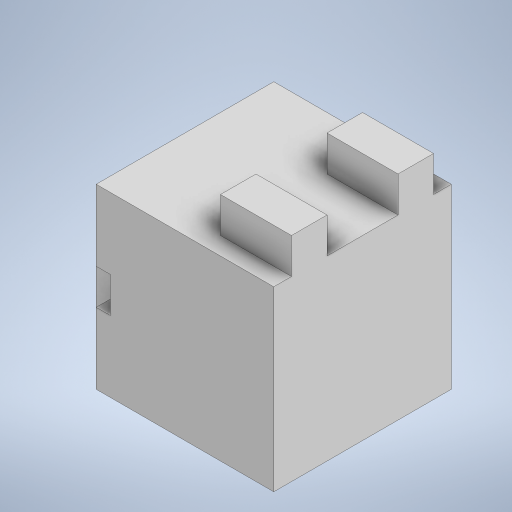
# Autodesk Inventor part: hlava
Saved by Autodesk Inventor 2024 (Build 280153000, 153)
## iProperties
Created: 2025-11-04
Part Number: hlava
Material: Všeobecné
Document SubType Name: Modeling
Designer: zak
Density: 1 g/cm^3
Appearance: Výchozí
Author: zak
Autodesk Inventor part; units mm, degrees
ref_plane "YZ Plane" through (0, 0, 0) normal (1, 0, 0) x (0, 1, 0)
ref_plane "XZ Plane" through (0, 0, 0) normal (0, 1, 0) x (-1, 0, 0)
ref_plane "XY Plane" through (0, 0, 0) normal (0, 0, 1) x (1, 0, 0)
sketch "Náčrt1" plane through (0, 0, 0) normal (0, 0, 1) x (1, 0, 0)
  point P0 (0, 0)
sketch "Náčrt2" plane through (0, 0, 0) normal (0, 0, 1) x (1, 0, 0)
  line L0 (-12.5, 12.5) -> (12.5, 12.5)
  line L1 (12.5, 12.5) -> (12.5, -12.5)
  line L2 (12.5, -12.5) -> (-12.5, -12.5)
  line L3 (-12.5, -12.5) -> (-12.5, 12.5)
  line L4 (-17.5, 0) -> (17.5, 0) projected
  line L5 (0, -17.5) -> (0, 17.5) projected
  point P0 (0, 0)
  dimension "d0" = 25
  dimension "d1" = 25
  constraints: 8 end point, 2 parallel, 1 horizontal, 1 perpendicular, 2 other
  measures "d0" distance of L1.end L2.end
  measures "d1" distance of L0.end L1.end
extrude "Vysunutí1" add sketch "Náčrt2" along normal mid plane 25
sketch "Náčrt3" plane through (-12.5, -12.5, 12.5) normal (-1, 0, 0) x (0, 0, 1)
  line L0 (-25, 0) -> (0, 0) projected
  line L1 (-20, 10) -> (-5, 10)
  line L2 (-5, 10) -> (-5, 0)
  line L3 (-5, 0) -> (-20, 0)
  line L4 (-20, 0) -> (-20, 10)
  line L5 (-12.5, -5) -> (-12.5, 30) projected
  point P0 (-12.5, 12.5)
  point P1 (-20, 0)
  dimension "d4" = 15
  dimension "d5" = 10
  constraints: 8 end point, 2 parallel, 1 horizontal, 1 perpendicular, 1 point on line, 1 other
  measures "d4" distance between parallel lines of L2 L4
  measures "d5" distance between parallel lines of L0 L1
extrude "Vysunutí2" add sketch "Náčrt3" along normal blind 5
sketch "Náčrt4" plane through (-12.5, 12.5, 12.5) normal (0, 1, 0) x (1, 0, 0)
  line L0 (25, 22.5) -> (15, 22.5)
  line L1 (15, 22.5) -> (15, 17.5)
  line L2 (15, 17.5) -> (25, 17.5)
  line L3 (25, 17.5) -> (25, 22.5)
  line L4 (0, 25) -> (25, 25) projected
  line L5 (25, 0) -> (25, 25) projected
  line L6 (-11, 12.5) -> (31, 12.5) projected
  line L7 (25, 2.5) -> (15, 2.5)
  line L8 (15, 2.5) -> (15, 7.5)
  line L9 (15, 7.5) -> (25, 7.5)
  line L10 (25, 7.5) -> (25, 2.5)
  point P0 (12.5, 12.5)
  dimension "d8" = 10
  dimension "d9" = 5
  dimension "d10" = 2.5
  constraints: 16 end point, 4 symmetric about line, 2 parallel, 1 collinear, 1 horizontal, 1 perpendicular
  measures "d8" distance of L2.end L1.end
  measures "d9" distance of L1.end L0.end
  measures "d10" distance between parallel lines of L4 L0
extrude "Vysunutí3" add sketch "Náčrt4" along normal blind 5
sketch "Náčrt5" plane through (-17.5, -12.5, 12.5) normal (-1, 0, 0) x (0, 0, 1)
  line L0 (-12.5, -6) -> (-12.5, 36) projected
  line L1 (-15, 10) -> (-10, 10)
  line L2 (-10, 10) -> (-10, 5)
  line L3 (-10, 5) -> (-15, 5)
  line L4 (-15, 5) -> (-15, 10)
  line L5 (-5, 10) -> (-20, 10) projected
  point P0 (-12.5, 12.5)
  dimension "d17" = 5
  dimension "d18" = 5
  constraints: 8 end point, 2 parallel, 1 collinear, 1 horizontal, 1 perpendicular, 1 other
  measures "d17" distance of L2.end L3.end
  measures "d18" distance of L1.end L2.end
emboss "Reliéf2" sketch "Náčrt5" operation cut depth 1 direction (1, 0, 0)
sketch "Náčrt6" plane through (-12.5, -12.5, 12.5) normal (-1, 0, 0) x (0, 0, 1)
  line L0 (-25, 15) -> (-15, 15)
  line L1 (-15, 15) -> (-15, 10)
  line L2 (-15, 10) -> (-25, 10)
  line L3 (-25, 10) -> (-25, 15)
  line L4 (-15, 10) -> (-20, 10) projected
  line L5 (-25, 0) -> (-25, 25) projected
  line L6 (-30, 12.5) -> (5, 12.5) projected
  line L7 (-12.5, -6) -> (-12.5, 36) projected
  line L8 (0, 15) -> (-10, 15)
  line L9 (-10, 15) -> (-10, 10)
  line L10 (-10, 10) -> (0, 10)
  line L11 (0, 10) -> (0, 15)
  point P0 (-12.5, 12.5)
  dimension "d22" = 10
  dimension "d23" = 5
  constraints: 16 end point, 4 symmetric about line, 2 collinear, 2 parallel, 1 horizontal, 1 perpendicular
  measures "d22" distance of L1.end L2.end
  measures "d23" distance of L0.end L1.end
emboss "Reliéf3" sketch "Náčrt6" operation cut depth 2 direction (1, 0, 0)
